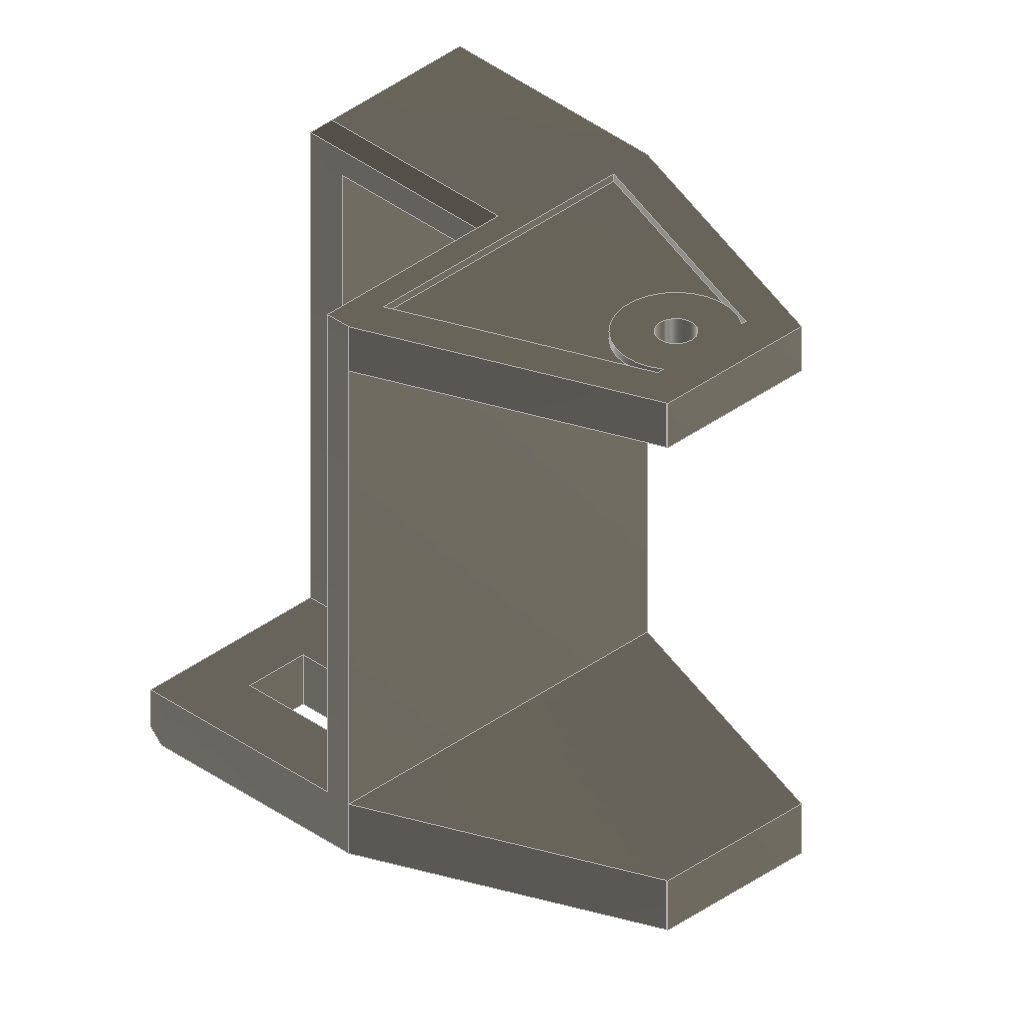
Coxa (Autodesk Fusion 360 design; units mm, degrees)
part number: 2026-10-13-14-01-52-453
Autodesk Fusion 360 part; units mm, degrees
sketch "CoxaFront" plane through (0, 0, 0) normal (0, 1, 0) x (1, 0, 0)
  line L0 (-78.705, -17.5316) -> (-91.295, -17.5316)
  line L1 (-91.295, -17.5316) -> (-91.295, 15.2684)
  line L2 (-91.295, 15.2684) -> (-78.705, 15.2684)
  line L3 (-78.705, 15.2684) -> (-78.705, -17.5316)
  circle A0 centre (-85, 4.2684) radius 2.5
  line L4 (-62.5, -18.3262) -> (-57.5, -18.3262) construction
  line L5 (-64, 17.6738) -> (-56, 17.6738) construction
  line L6 (-54.5013, -16.9371) -> (-54.5013, -20.5316)
  line L7 (-54.5013, -20.5316) -> (-94.295, -20.5316)
  line L8 (-94.295, 18.2684) -> (-54.5013, 18.2684)
  line L9 (-54.5013, 18.2684) -> (-54.5013, 14.6738)
  line L10 (-54.5013, -16.9371) -> (-75.705, -16.9371)
  line L11 (-75.705, -16.9371) -> (-75.705, 14.6738)
  line L12 (-75.705, 14.6738) -> (-54.5013, 14.6738)
  line L13 (-94.295, 18.2684) -> (-94.295, -20.5316)
  line L14 (-56, 14.6738) -> (-64, 14.6738)
  line L15 (-91.295, -17.5316) -> (-78.705, -17.5316)
  line L16 (-78.705, -17.5316) -> (-78.705, -13.0316)
  line L17 (-78.705, -13.0316) -> (-91.295, -13.0316)
  line L18 (-91.295, -13.0316) -> (-91.295, -17.5316)
  line L19 (-91.295, 15.2684) -> (-78.705, 15.2684)
  line L20 (-78.705, 15.2684) -> (-78.705, 10.7684)
  line L21 (-78.705, 10.7684) -> (-91.295, 10.7684)
  line L22 (-91.295, 10.7684) -> (-91.295, 15.2684)
  line L23 (-91.295, 4.2684) -> (-78.705, 4.2684) construction
  circle A1 centre (-85, 12.7684) radius 1.25
  circle A2 centre (-85, -15.0316) radius 1.25
  line L24 (-91.295, -17.5316) -> (-91.295, -20.5316)
  line L25 (-78.705, -17.5316) -> (-78.705, -20.5316)
  line L26 (-91.295, 15.2684) -> (-91.295, 18.2684)
  line L27 (-78.705, 15.2684) -> (-78.705, 18.2684)
  line L28 (-54.5013, 22.2684) -> (-94.295, 22.2684)
  line L29 (-94.295, 22.2684) -> (-94.295, 18.2684)
  line L30 (-94.295, 18.2684) -> (-54.5013, 18.2684)
  line L31 (-54.5013, 18.2684) -> (-54.5013, 22.2684)
  line L32 (-75.705, 14.6738) -> (-75.705, 18.2684)
  point P0 (-60, 0)
  dimension "d1" = 0
  dimension "d2" = 0
  dimension "d3" = 0
  dimension "d4" = 25
  dimension "d5" = 3
  dimension "d6" = 3
  dimension "d7" = 0
  dimension "d8" = 0
  dimension "d9" = 0
  dimension "d10" = 9.4987
  dimension "d11" = 0.5945
  dimension "d12" = 4.5
  dimension "d13" = 4.5
  dimension "d14" = 2.5
  dimension "d15" = 0
  dimension "d16" = 4
  constraint horizontal L0
  constraint vertical L1
  constraint horizontal L2
  constraint vertical L3
  constraint perpendicular L4 L6
  constraint parallel L7 L8
  constraint perpendicular L8 L9
  constraint perpendicular L4 L11
  constraint horizontal L12
  constraint perpendicular L7 L13
  constraint horizontal L10
  constraint collinear L12 L14
  constraint collinear L6 L9
  constraint equal L6 L9
  constraint horizontal L15
  constraint vertical L16
  constraint horizontal L17
  constraint vertical L18
  constraint horizontal L19
  constraint vertical L20
  constraint horizontal L21
  constraint vertical L22
  constraint coincident L1 L23.start
  constraint coincident L3 L23.end
  constraint perpendicular L3 L23
  constraint midpoint A0.centre L23
  constraint collinear L3 L20
  constraint collinear L3 L16
  constraint coincident L7 L24.end
  constraint perpendicular L7 L24
  constraint coincident L7 L25.end
  constraint perpendicular L7 L25
  constraint coincident L8 L26.end
  constraint perpendicular L8 L26
  constraint coincident L8 L27.end
  constraint perpendicular L8 L27
  constraint horizontal L28
  constraint vertical L29
  constraint horizontal L30
  constraint vertical L31
  constraint coincident L13 L8.start
  constraint collinear L8 L30
  constraint collinear L9 L31
  constraint coincident L8 L32.end
  constraint perpendicular L8 L32
  measures "d2" distance of L1 L3
  measures "d3" distance of L0.end L1.end
  measures "d4" horizontal distance of A0.centre P0
  measures "d5" distance of L3 L11
  measures "d6" distance of L0 L7
  measures "d7" distance of L2 L8
  measures "d8" distance of L1 L13
  measures "d10" distance of L9 L14.end
  measures "d11" distance of L2 L14
  measures "d12" distance of L0.end L17.end
  measures "d13" distance of L1.end L21.end
  measures "d14" diameter of A1
  measures "d16" distance of L28.start L8.end
sketch "CoxaTop" plane through (0, 0, 0) normal (0, 0, 1) x (1, 0, 0)
  line L0 (-78.705, -15) -> (-91.295, -15)
  line L1 (-91.295, -15) -> (-91.295, 13)
  line L2 (-91.295, 13) -> (-78.705, 13)
  line L3 (-78.705, 13) -> (-78.705, -15)
  line L4 (-78.705, 0) -> (-91.295, 0) construction
  line L5 (-82.5, 13) -> (-87.5, 13)
  line L6 (-87.5, 13) -> (-87.5, 17)
  line L7 (-87.5, 17) -> (-82.5, 17)
  line L8 (-82.5, 17) -> (-82.5, 13)
  line L9 (-81, -19) -> (-89, -19)
  line L10 (-89, -19) -> (-89, -16)
  line L11 (-89, -16) -> (-81, -16)
  line L12 (-81, -16) -> (-81, -19)
  line L13 (-94.295, 13) -> (-54.5013, 13)
  line L14 (-54.5013, 13) -> (-54.5013, -15)
  line L15 (-54.5013, -15) -> (-94.295, -15)
  line L16 (-94.295, -15) -> (-94.295, 13)
  line L17 (-80, -15) -> (-80, 5) construction
  line L18 (-78.705, 5) -> (-91.295, 5)
  line L19 (-91.295, 5) -> (-91.295, 7)
  line L20 (-91.295, 7) -> (-78.705, 7)
  line L21 (-78.705, 7) -> (-78.705, 5)
  line L22 (-90, -5) -> (-80, -5)
  line L23 (-80, -5) -> (-80, -10)
  line L24 (-80, -10) -> (-90, -10)
  line L25 (-90, -10) -> (-90, -5)
  line L26 (-90, -5) -> (-80, -10) construction
  line L27 (-85, -15) -> (-85, 0) construction
  point P0 (-78.705, 0)
  point P1 (-94.295, 0)
  point P2 (-54.5013, 0)
  dimension "d17" = 0
  dimension "d18" = 0
  dimension "d19" = 15
  dimension "d20" = 5
  dimension "d21" = 0
  dimension "d22" = 8
  dimension "d23" = 3
  dimension "d24" = 1
  dimension "d25" = 36.7937
  dimension "d26" = 20
  dimension "d27" = 0
  dimension "d28" = 2
  dimension "d29" = 6
  dimension "d30" = 10
  dimension "d31" = 5
  constraint horizontal L0
  constraint vertical L1
  constraint horizontal L2
  constraint vertical L3
  constraint coincident L3 P0
  constraint horizontal L5
  constraint vertical L6
  constraint horizontal L7
  constraint vertical L8
  constraint coincident L2 L5.start
  constraint midpoint L2 L5
  constraint horizontal L9
  constraint vertical L10
  constraint horizontal L11
  constraint vertical L12
  constraint perpendicular L3 L13
  constraint perpendicular L13 L14
  constraint perpendicular L3 L15
  constraint vertical L16
  constraint coincident L16 P1
  constraint coincident L14 P2
  constraint collinear L0 L15
  constraint horizontal L2.end L13.start
  constraint perpendicular L4 L17
  constraint horizontal L18
  constraint vertical L19
  constraint horizontal L20
  constraint vertical L21
  constraint coincident L3 L18.start
  constraint horizontal L22
  constraint vertical L23
  constraint horizontal L24
  constraint vertical L25
  constraint midpoint L0 L27.start
  constraint midpoint L4 L27.end
  constraint midpoint L26 L27
  measures "d17" distance of L0 L2
  measures "d18" distance of L1 L3
  measures "d19" distance of L0 L4.end
  measures "d20" distance of L5.start L5.end
  measures "d21" distance of L5.start L7.end
  measures "d22" distance of L9.start L9.end
  measures "d23" distance of L9.start L11.end
  measures "d24" distance of L0 L11
  measures "d25" distance of L1 L14
  measures "d26" distance of L17.start L17.end
  measures "d27" distance of L18.start L18.end
  measures "d28" distance of L18.start L20.end
  measures "d29" distance of L13 L20
  measures "d30" distance of L22.start L22.end
  measures "d31" distance of L22.start L24.end
extrude "Extrude1" add sketch "CoxaFront" along normal up to surface (13 mm away) and the other way up to surface (15 mm away) contours L0 L7 L15 L24 L25 | L3 L6 L7 L8 L10 L11 L16 L20 L25 L27 L30 L32 | L1 L7 L8 L13 L18 L22 L24 L26 L30 | L2 L8 L19 L26 L27 L30 | L8 L9 L12 L14 L30 L32
extrude "Extrude2" add sketch "CoxaTop" along normal up to surface (-15.2684 mm away) and the other way up to surface (-17.5316 mm away) contours L1 L3 L18 L19 L20 L21
extrude "Extrude3" cut sketch "CoxaFront" along normal up to surface (7 mm away) contours L1 L3 L17 L21 | A0 | A1 | A2
sketch "Sketch1" plane through (0, 0, 16.9371) normal (0, 0, -1) x (1, 0, 0)
  line L0 (-75.705, -13) -> (-54.5013, -13)
  line L1 (-54.5013, -13) -> (-54.5013, 15)
  line L2 (-54.5013, 15) -> (-75.705, 15)
  line L3 (-75.705, 15) -> (-75.705, -13)
  line L4 (-54.5013, 0) -> (-75.705, 0)
  circle A0 centre (-60, 0) radius 1.46
  point P0 (-60, 0)
  dimension "d302" = 2.92
  constraint coincident L1 L4.start
  constraint coincident L3 L4.end
  constraint perpendicular L3 L4
  constraint coincident P0 A0.centre
  measures "d302" diameter of A0
extrude "Extrude4" cut sketch "Sketch1" against normal up to surface (3.5945 mm away) contours L4 A0 | L4 A0
extrude "Extrude5" cut sketch "CoxaFront" along normal blind -15 and the other way blind 0 contours L0 L7 L15 L24 L25
extrude "Extrude6" cut sketch "CoxaFront" against normal up to surface (15 mm away) contours L2 L8 L19 L26 L27 L30
extrude "Extrude7" cut sketch "CoxaFront" against normal up to surface (15 mm away) contours L1 L7 L8 L13 L18 L22 L24 L26 L30
sketch "Sketch9" plane through (0, 0, 20.5316) normal (0, 0, 1) x (-1, 0, 0)
  circle A0 centre (60, 0) radius 1.46
  line L0 (94.295, 0) -> (78.705, 0)
  line L1 (78.705, 0) -> (78.705, 15)
  line L2 (78.705, 15) -> (54.5013, 15)
  line L3 (54.5013, 15) -> (54.5013, -13)
  line L4 (54.5013, -13) -> (94.295, -13)
  line L5 (94.295, -13) -> (94.295, 0)
  line L6 (71, -6.295) -> (38.2, -6.295)
  line L7 (38.2, 6.295) -> (71, 6.295)
  line L8 (75.705, 15) -> (54.6, 6.295)
  line L9 (75.705, 15) -> (75.705, -13) construction
  line L10 (75.705, -13) -> (54.6, -6.295)
  point P0 (75.705, 15)
  constraint coincident P0 L8.start
  constraint midpoint L7 L8.end
  constraint coincident L4 L9.end
  constraint midpoint L6 L10.end
  constraint vertical L9
extrude "Extrude8" cut sketch "Sketch9" against normal up to surface (38.8 mm away) contours L3 L4 L6 L10 | L2 L3 L7 L8
shell "Shell2" thickness 3 removed faces 1 at (-69.67, -7.0983, -18.2684)
shell "Shell3" thickness 3 removed faces 1 at (-70.335, -4.1434, 20.5316)
chamfer "Chamfer6" distance 1 angle 45 3 edges at (-78.705, -15, 1.1316) (-78.705, -7.5, 20.5316) (-86.5, 0, 20.5316) tangent chain off
chamfer "Chamfer7" distance 1 angle 45 2 edges at (-94.295, 7, 20.5316) (-94.295, 6.5, -18.2684) tangent chain off
extrude "Extrude9" cut 1 faces at (-69.67, -4.0166, -17.6738) along direction (0, 0, 1) up to surface (3 mm away)
extrude "Extrude10" cut sketch "CoxaFront" along normal blind -15 and the other way up to surface (-13 mm away) contours L8 L9 L12 L14 L30 L32
extrude "Extrude11" add sketch "CoxaFront" along normal up to surface (-15 mm away) and the other way up to surface (-13 mm away) contours L8 L28 L29 L30 L31
delete_face "DeleteFace1" 1 faces at (-93.9617, 8.6667, -17.6017)
extrude "Extrude12" cut sketch "Sketch9" against normal up to surface (42.8 mm away) contours L3 L4 L6 L10 | L2 L3 L7 L8
chamfer "Chamfer8" distance 1 angle 45 1 edges at (-94.295, -1, -22.2684) tangent chain off
extrude "Extrude13" cut sketch "CoxaTop" against normal up to surface (22.2684 mm away) contours L22 L23 L24 L25
equation "d302 = heatsink_OD"
equation "heatsink_OD = 2.92 mm"
equation "d1 = ServoHorn"
equation "d2 = ServoWidth"
equation "d3 = ServoLength"
equation "d7 = d75"
equation "d8 = d74"
equation "d9 = ServoHornOffset"
equation "d15 = d279"
equation "d17 = ServoDepth"
equation "d18 = ServoWidth"
equation "d21 = HornLength"
equation "d27 = ServoWidth"
